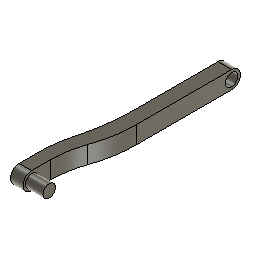
connecting rod (Autodesk Fusion 360 design; units mm, degrees)
part number: 2026-03-27-15-36-50-826
Autodesk Fusion 360 part; units mm, degrees
sketch "Sketch1" plane through (0, 0, 0) normal (1, 0, 0) x (0, 1, 0)
  circle A0 centre (0, 0) radius 2.5
  dimension "d1" = 5
  constraint coincident A0.centre origin
  measures "d1" diameter of A0
extrude "Extrude1" add sketch "Sketch1" along normal blind 7
sketch "Sketch2" plane through (0, 0, 0) normal (-1, 0, 0) x (0, -1, 0)
  circle A0 centre (0, 0) radius 2.5
  circle A1 centre (0, 0) radius 3.5
  dimension "d4" = 7
  constraint coincident A0.centre A1.centre
  measures "d4" diameter of A1
extrude "Extrude2" add sketch "Sketch2" along normal blind 5 contours A0 | A1
sketch "Sketch3" plane through (-5, 0, 0) normal (-1, 0, 0) x (0, -1, 0)
  circle A0 centre (0, 0) radius 3.5
  circle A1 centre (0, 0) radius 3.5
  line L0 (0, 3.5) -> (-75, 3.5)
  line L1 (-78.5, 0) -> (-78.5, -3.5) construction
  line L2 (-78.5, -3.5) -> (0, -3.5)
  line L3 (0, -3.5) -> (0, 3.5)
  arc A2 (-75, 3.5) -> (-75, -3.5) centre (-75, 0) ccw
  dimension "d7" = 75
  constraint horizontal L0
  constraint vertical L1
  constraint horizontal L2
  constraint vertical L3
  constraint coincident A1 L0.start
  constraint coincident A1 L2.end
  constraint tangent A0 L0
  constraint tangent L0 A2
  constraint tangent L2 A2
  constraint tangent L1 A2
  constraint coincident L1.start A2
  constraint coincident L2 A2.end
  constraint coincident L0 A2.start
  constraint coincident L0.end A2.start
  measures "d7" distance of L0.start L0.end
extrude "Extrude3" add sketch "Sketch3" against normal up to surface (5 mm away) contours A0 A1 L0 L2 A2
sketch "Sketch4" plane through (0, 0, 0) normal (1, 0, 0) x (0, 1, 0)
  line L0 (0, -3.5) -> (75, -3.5)
  arc A0 (75, -3.5) -> (75, 3.5) centre (75, 0) ccw
  line L1 (75, 3.5) -> (0, 3.5)
  arc A1 (0, 3.5) -> (0, -3.5) centre (0, 0) ccw
  circle A2 centre (0, 0) radius 2.5
  circle A3 centre (75, 0) radius 2.5
  dimension "d10" = 5
  constraint concentric A0 A3
  measures "d10" diameter of A3
extrude "Extrude4" add sketch "Sketch4" along normal up to surface (7 mm away) contours A3
extrude "Extrude5" cut 1 faces at (7, 75.3045, -1.0241) along direction (-1, 0, 0) blind 33
sketch "Sketch5" plane through (-5, 0, 0) normal (-1, 0, 0) x (0, -1, 0)
  circle A0 centre (-75, 0) radius 2.5
  arc A1 (0, -3.5) -> (0, 3.5) centre (0, 0) ccw
  line L0 (0, 3.5) -> (-75, 3.5)
  arc A2 (-75, 3.5) -> (-75, -3.5) centre (-75, 0) ccw
  line L1 (-75, -3.5) -> (0, -3.5)
  line L2 (-15, -3.5) -> (-15, 3.5)
  dimension "d15" = 15
  constraint coincident L1 L2.start
  constraint coincident L0 L2.end
  constraint perpendicular L0 L2
  measures "d15" distance of A1.centre L2
extrude "Extrude6" add sketch "Sketch5" against normal blind 10 contours L0 A2 L1 L2
sketch "Sketch6" plane through (5, 0, 0) normal (1, 0, 0) x (0, 1, 0)
  circle A0 centre (75, 0) radius 2.5
  line L0 (15, 3.5) -> (15, -3.5)
  line L1 (15, -3.5) -> (75, -3.5)
  arc A1 (75, -3.5) -> (75, 3.5) centre (75, 0) ccw
  line L2 (75, 3.5) -> (15, 3.5)
extrude "Extrude7" cut sketch "Sketch6" against normal blind 8 from surface at -5.5
fillet "Fillet1" radius 84 1 edges at (-0.5, 15, 0)
fillet "Fillet2" radius 50.5 1 edges at (5, 15, 0)
fillet "Fillet3" radius 48.5 1 edges at (-5, 15, 0)
fillet "Fillet3" radius 38.5 1 edges at (0, 15, 0)
